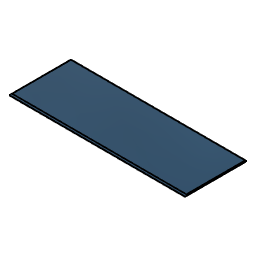
Lid_PRINT (Autodesk Fusion 360 design; units mm, degrees)
Autodesk Fusion 360 part; units mm, degrees
sketch "Sketch1" plane through (0, 0, 0) normal (0, 0, 1) x (1, 0, 0)
  line L0 (0, 0) -> (232.6, 0)
  line L1 (232.6, 0) -> (232.6, 81.6)
  line L2 (232.6, 81.6) -> (0, 81.6)
  line L3 (0, 81.6) -> (0, 0)
  line L4 (1.2, 80.4) -> (231.4, 80.4)
  line L5 (231.4, 80.4) -> (231.4, 3)
  line L6 (231.4, 3) -> (1.2, 3)
  line L7 (1.2, 3) -> (1.2, 80.4)
  dimension "d1" = 1.2
  dimension "d2" = 1.2
  dimension "d3" = 3
  dimension "d4" = 1.2
  dimension "d5" = 232.6
  dimension "d10" = 81.6
  constraint horizontal L0
  constraint vertical L1
  constraint horizontal L2
  constraint vertical L3
  constraint coincident L0.start L3.end
  constraint horizontal L4
  constraint vertical L5
  constraint horizontal L6
  constraint vertical L7
  measures "d1" distance of L2 L4
  measures "d2" distance of L1 L5
  measures "d3" distance of L0 L6
  measures "d4" distance of L3 L7
  measures "d5" distance of L1.end L2.end
  measures "d10" distance of L0.start L2.end
extrude "Extrude1" add sketch "Sketch1" along normal blind 0.8
extrude "Extrude2" add sketch "Sketch1" along normal blind 1.3 contours L4 L5 L6 L7
